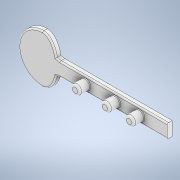
# Autodesk Inventor part: 4
Saved by Autodesk Inventor 2020 (Build 240168000, 168)
## iProperties
Created: 2022-06-19
Part Number: 4
Material: Generic
Document SubType Name: Modeling
Designer: drago
Density: 1 g/cm^3
Appearance: Default(3)
Author: drago
Autodesk Inventor part; units mm, degrees
ref_plane "YZ Plane" through (0, 0, 0) normal (1, 0, 0) x (0, 1, 0)
ref_plane "XZ Plane" through (0, 0, 0) normal (0, 1, 0) x (-1, 0, 0)
ref_plane "XY Plane" through (0, 0, 0) normal (0, 0, 1) x (1, 0, 0)
sketch "Sketch1" plane through (0, 0, 0) normal (0, 0, 1) x (1, 0, 0)
  line L0 (0, 0) -> (-180, 0)
  line L1 (-180, 0) -> (-180, 20)
  line L2 (-180, 20) -> (0, 20)
  line L3 (0, 20) -> (0, 0)
  dimension "d0" = 180
  dimension "d1" = 20
  constraints: 8 end point, 2 parallel, 1 horizontal, 1 perpendicular
  measures "d0" distance of L1.end L2.end
  measures "d1" distance of L2.end L0.start
extrude "Extrusion1" add sketch "Sketch1" along normal blind 7
sketch "Sketch2" plane through (0, 0, 7) normal (0, 0, 1) x (1, 0, 0)
  line L0 (0, 20) -> (-180, 20) construction
  line L1 (-15, 20) -> (-15, 0) construction
  line L2 (-180, 0) -> (0, 0) construction
  line L3 (-150, 20) -> (-150, 0) construction
  line L4 (-180, 20) -> (-180, 0) projected
  line L5 (0, 0) -> (0, 20) projected
  line L6 (-135, 20) -> (-135, 0) construction
  circle A0 centre (-118, 10) radius 6.75
  circle A1 centre (-75, 10) radius 6.75
  circle A2 centre (-40, 10) radius 6.75
  line L7 (-118, 10) -> (-118, -4.5117)
  line L8 (-118, -4.5117) -> (-75, -4.5117)
  line L9 (-75, -4.5117) -> (-75, 10)
  line L10 (-75, -4.5117) -> (-40, -4.5117)
  line L11 (-40, -4.5117) -> (-40, 10)
  dimension "d5" = 15
  dimension "d6" = 150
  dimension "d7" = 15
  dimension "d8" = 13.5
  dimension "d9" = 13.5
  dimension "d10" = 13.5
  dimension "d12" = 17
  dimension "d13" = 25
  dimension "d88" = 43
  constraints: 16 end point, 6 point on line, 5 perpendicular, 3 centre point, 2 vertical, 1 horizontal
  measures "d5" distance between parallel lines of L5 L1
  measures "d6" distance between parallel lines of L5 L3
  measures "d7" distance between parallel lines of L6 L3
  measures "d8" diameter of A0
  measures "d9" diameter of A1
  measures "d10" diameter of A2
  measures "d12" distance from line of L6 L7.start
  measures "d13" distance from line of L1 L11.end
  measures "d88" distance of L7.end L8.end
extrude "Extrusion2" add sketch "Sketch2" along normal blind 15.3
sketch "Sketch4" plane through (0, 0, 7) normal (0, 0, 1) x (1, 0, 0)
  circle A0 centre (-180, 10) radius 35
  line L0 (-180, 20) -> (-180, 0) projected
  line L1 (-180, 10) -> (-174.2939, 10)
  line L2 (-180, 45) -> (-180, -25)
  ellipse E0 centre (-180, 22) end of major axis (-212.8786, 22) minor radius 12
  ellipse E1 centre (-180, -2) end of major axis (-212.8786, -2) minor radius 12
  ellipse E2 centre (-180, 10) end of major axis (-180, 44.9576) minor radius 20.5268
  line L3 (0, 0) -> (0, 20) projected
  line L4 (0, 10) -> (-155, 10)
  line L5 (-180, 0) -> (0, 0) projected
  line L6 (0, 20) -> (-180, 20) projected
  arc A1 (-180, 45) -> (-146.459, 20) centre (-150.7295, 49.2705) ccw
  arc A2 (-146.459, 0) -> (-180, -25) centre (-150.7295, -29.2705) ccw
  point P0 (-180, 19)
  point P1 (-180, 1)
  point P2 (-195.687, 32.5461)
  point P3 (-211.287, 25.6884)
  point P4 (-211.287, -5.6884)
  point P5 (-195.687, -12.5461)
  point P6 (-164.313, -12.5461)
  point P7 (-148.713, -5.6884)
  point P8 (-148.713, 25.6884)
  point P9 (-164.313, 32.5461)
  point P10 (-155, 20)
  point P11 (-155, 0)
  point P12 (-180, 44.9576)
  point P13 (-180, -24.9576)
  point P14 (-160.5919, -1.3826)
  point P15 (-160.5919, 21.3826)
  dimension "d21" = 70
  dimension "d65" = 70
  dimension "d66" = 23
  dimension "d67" = 23
  dimension "d83" = 0
  dimension "d84" = 155
  constraints: 10 point on circle, 6 end point, 5 point on line, 3 centre point, 3 coincident, 2 horizontal, 2 midpoint, 2 vertical, 8 other
  measures "d21" diameter of A0
  measures "d65" distance of L2.start L2.end
  measures "d66" distance of L2.start point (-180, 22)
  measures "d67" distance of L2.end point (-180, -2)
  measures "d83" distance of L1.start A0.centre
  measures "d84" distance of L4.start L4.end
extrude "Extrusion4" add sketch "Sketch4" against normal blind 7 contours A0 A2 E1 E2 E0 A1 | A1 E0 L6 | L5 E1 A2 | E0 A1 L6 | E0 E2 L6 A1 | L5 A2 E1 | A2 L5 E2 E1 | L6 E2 A1 | E2 E1 E0 | E0 L0 L6 E2 | A2 E2 L5 | E2 L5 L0 E1 | L2 E2 E0 A0 | E2 A1 E0 | E0 A1 E2 | L6 L2 E0 A1 E2 | E0 E2 L2 L0 | E1 E2 E0 | L0 L2 E1 E2 | A0 E1 E2 L2 | E2 A2 E1 | E1 A2 E2 | E2 A2 E1 L2 L5 | E0 E2 A0 | E2 A1 E0 L2 | L2 E0 E2 | E2 E1 A0 E0 | E2 E1 A0 | E2 E1 L2 | L2 E1 A2 E2
fillet "Fillet6" radius 1 3 edges at (-124.75, 10, 7) (-81.75, 10, 7) (-46.75, 10, 7)
fillet "Fillet7" radius 3 3 edges at (-124.75, 10, 22.3) (-81.75, 10, 22.3) (-46.75, 10, 22.3)
fillet "Fillet8" radius 2 7 edges at (-77.5, 0, 7) (-77.5, 20, 7) (-157.8297, 20.5549, 7) (-157.8297, -0.5549, 7) (-168.0804, -18.46, 7) (-168.0804, 38.46, 7) (-215, 10, 7)
body "Solid1"
